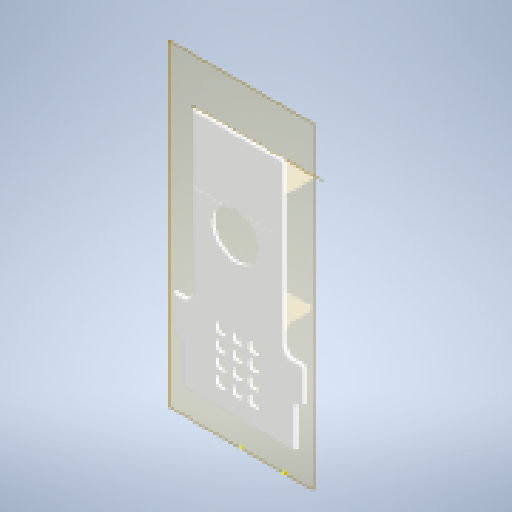
# Autodesk Inventor part: низдляакума
Saved by Autodesk Inventor 2024.2 (Build 282272000, 272)
## iProperties
Created: 2026-09-03
Part Number: низдляакума
Material: PLA
Document SubType Name: Modeling
Designer: katya_notebook
Density: 1.24 g/cm^3
Appearance: Типовые
Author: katya_notebook
Autodesk Inventor part; units mm, degrees
ref_plane "YZ Plane" through (0, 0, 0) normal (1, 0, 0) x (0, 1, 0)
ref_plane "XZ Plane" through (0, 0, 0) normal (0, 1, 0) x (-1, 0, 0)
ref_plane "XY Plane" through (0, 0, 0) normal (0, 0, 1) x (1, 0, 0)
ref_plane "РабПлоскость1" through (0, 0, 0) normal (0, 0, 1) x (1, 0, 0)
sketch "Эскиз1" plane through (0, 0, 0) normal (0, 0, 1) x (1, 0, 0)
  line L0 (-33.5, 89.193196) -> (-33.5, 206.15018)
  line L1 (-33.5, 206.15018) -> (33.5, 206.15018)
  line L2 (33.5, 206.15018) -> (33.5, 89.193196)
  line L3 (33.5, 89.193196) -> (-33.5, 89.193196)
  arc A0 (-15.5, 209.5) -> (-15.5, 222.5) centre (-15.5, 216) ccw
  line L4 (-30.5, 209.5) -> (-15.5, 209.5)
  arc A1 (-30.5, 222.5) -> (-30.5, 209.5) centre (-30.5, 216) ccw
  line L5 (-15.5, 222.5) -> (-30.5, 222.5)
  arc A2 (21.25, 83.001313) -> (23.75, 80.501313) centre (23.75, 83.001313) ccw
  line L6 (21.25, 83.001313) -> (21.25, 85.501313)
  arc A3 (23.75, 88.001313) -> (21.25, 85.501313) centre (23.75, 85.501313) ccw
  line L7 (23.75, 88.001313) -> (26.25, 88.001313)
  arc A4 (28.75, 85.501313) -> (26.25, 88.001313) centre (26.25, 85.501313) ccw
  line L8 (28.75, 85.501313) -> (28.75, 83.001313)
  arc A5 (26.25, 80.501313) -> (28.75, 83.001313) centre (26.25, 83.001313) ccw
  line L9 (26.25, 80.501313) -> (23.75, 80.501313)
  arc A6 (8.75, 83.001313) -> (11.25, 80.501313) centre (11.25, 83.001313) ccw
  line L10 (8.75, 83.001313) -> (8.75, 85.501313)
  arc A7 (11.25, 88.001313) -> (8.75, 85.501313) centre (11.25, 85.501313) ccw
  line L11 (11.25, 88.001313) -> (13.75, 88.001313)
  arc A8 (16.25, 85.501313) -> (13.75, 88.001313) centre (13.75, 85.501313) ccw
  line L12 (16.25, 85.501313) -> (16.25, 83.001313)
  arc A9 (13.75, 80.501313) -> (16.25, 83.001313) centre (13.75, 83.001313) ccw
  line L13 (13.75, 80.501313) -> (11.25, 80.501313)
  arc A10 (-3.75, 83.001313) -> (-1.25, 80.501313) centre (-1.25, 83.001313) ccw
  line L14 (-3.75, 83.001313) -> (-3.75, 85.501313)
  arc A11 (-1.25, 88.001313) -> (-3.75, 85.501313) centre (-1.25, 85.501313) ccw
  line L15 (-1.25, 88.001313) -> (1.25, 88.001313)
  arc A12 (3.75, 85.501313) -> (1.25, 88.001313) centre (1.25, 85.501313) ccw
  line L16 (3.75, 85.501313) -> (3.75, 83.001313)
  arc A13 (1.25, 80.501313) -> (3.75, 83.001313) centre (1.25, 83.001313) ccw
  line L17 (1.25, 80.501313) -> (-1.25, 80.501313)
  arc A14 (-16.25, 83.001313) -> (-13.75, 80.501313) centre (-13.75, 83.001313) ccw
  line L18 (-16.25, 83.001313) -> (-16.25, 85.501313)
  arc A15 (-13.75, 88.001313) -> (-16.25, 85.501313) centre (-13.75, 85.501313) ccw
  line L19 (-13.75, 88.001313) -> (-11.25, 88.001313)
  arc A16 (-8.75, 85.501313) -> (-11.25, 88.001313) centre (-11.25, 85.501313) ccw
  line L20 (-8.75, 85.501313) -> (-8.75, 83.001313)
  arc A17 (-11.25, 80.501313) -> (-8.75, 83.001313) centre (-11.25, 83.001313) ccw
  line L21 (-11.25, 80.501313) -> (-13.75, 80.501313)
  arc A18 (-28.75, 83.001313) -> (-26.25, 80.501313) centre (-26.25, 83.001313) ccw
  line L22 (-28.75, 83.001313) -> (-28.75, 85.501313)
  arc A19 (-26.25, 88.001313) -> (-28.75, 85.501313) centre (-26.25, 85.501313) ccw
  line L23 (-26.25, 88.001313) -> (-23.75, 88.001313)
  arc A20 (-21.25, 85.501313) -> (-23.75, 88.001313) centre (-23.75, 85.501313) ccw
  line L24 (-21.25, 85.501313) -> (-21.25, 83.001313)
  arc A21 (-23.75, 80.501313) -> (-21.25, 83.001313) centre (-23.75, 83.001313) ccw
  line L25 (-23.75, 80.501313) -> (-26.25, 80.501313)
  arc A22 (21.25, 71.334646) -> (23.75, 68.834646) centre (23.75, 71.334646) ccw
  line L26 (21.25, 71.334646) -> (21.25, 73.834646)
  arc A23 (23.75, 76.334646) -> (21.25, 73.834646) centre (23.75, 73.834646) ccw
  line L27 (23.75, 76.334646) -> (26.25, 76.334646)
  arc A24 (28.75, 73.834646) -> (26.25, 76.334646) centre (26.25, 73.834646) ccw
  line L28 (28.75, 73.834646) -> (28.75, 71.334646)
  arc A25 (26.25, 68.834646) -> (28.75, 71.334646) centre (26.25, 71.334646) ccw
  line L29 (26.25, 68.834646) -> (23.75, 68.834646)
  arc A26 (8.75, 71.334646) -> (11.25, 68.834646) centre (11.25, 71.334646) ccw
  line L30 (8.75, 71.334646) -> (8.75, 73.834646)
  arc A27 (11.25, 76.334646) -> (8.75, 73.834646) centre (11.25, 73.834646) ccw
  line L31 (11.25, 76.334646) -> (13.75, 76.334646)
  arc A28 (16.25, 73.834646) -> (13.75, 76.334646) centre (13.75, 73.834646) ccw
  line L32 (16.25, 73.834646) -> (16.25, 71.334646)
  arc A29 (13.75, 68.834646) -> (16.25, 71.334646) centre (13.75, 71.334646) ccw
  line L33 (13.75, 68.834646) -> (11.25, 68.834646)
  arc A30 (-3.75, 71.334646) -> (-1.25, 68.834646) centre (-1.25, 71.334646) ccw
  line L34 (-3.75, 71.334646) -> (-3.75, 73.834646)
  arc A31 (-1.25, 76.334646) -> (-3.75, 73.834646) centre (-1.25, 73.834646) ccw
  line L35 (-1.25, 76.334646) -> (1.25, 76.334646)
  arc A32 (3.75, 73.834646) -> (1.25, 76.334646) centre (1.25, 73.834646) ccw
  line L36 (3.75, 73.834646) -> (3.75, 71.334646)
  arc A33 (1.25, 68.834646) -> (3.75, 71.334646) centre (1.25, 71.334646) ccw
  line L37 (1.25, 68.834646) -> (-1.25, 68.834646)
  arc A34 (-16.25, 71.334646) -> (-13.75, 68.834646) centre (-13.75, 71.334646) ccw
  line L38 (-16.25, 71.334646) -> (-16.25, 73.834646)
  arc A35 (-13.75, 76.334646) -> (-16.25, 73.834646) centre (-13.75, 73.834646) ccw
  line L39 (-13.75, 76.334646) -> (-11.25, 76.334646)
  arc A36 (-8.75, 73.834646) -> (-11.25, 76.334646) centre (-11.25, 73.834646) ccw
  line L40 (-8.75, 73.834646) -> (-8.75, 71.334646)
  arc A37 (-11.25, 68.834646) -> (-8.75, 71.334646) centre (-11.25, 71.334646) ccw
  line L41 (-11.25, 68.834646) -> (-13.75, 68.834646)
  arc A38 (-28.75, 71.334646) -> (-26.25, 68.834646) centre (-26.25, 71.334646) ccw
  line L42 (-28.75, 71.334646) -> (-28.75, 73.834646)
  arc A39 (-26.25, 76.334646) -> (-28.75, 73.834646) centre (-26.25, 73.834646) ccw
  line L43 (-26.25, 76.334646) -> (-23.75, 76.334646)
  arc A40 (-21.25, 73.834646) -> (-23.75, 76.334646) centre (-23.75, 73.834646) ccw
  line L44 (-21.25, 73.834646) -> (-21.25, 71.334646)
  arc A41 (-23.75, 68.834646) -> (-21.25, 71.334646) centre (-23.75, 71.334646) ccw
  line L45 (-23.75, 68.834646) -> (-26.25, 68.834646)
  arc A42 (21.25, 59.66798) -> (23.75, 57.16798) centre (23.75, 59.66798) ccw
  line L46 (21.25, 59.66798) -> (21.25, 62.16798)
  arc A43 (23.75, 64.66798) -> (21.25, 62.16798) centre (23.75, 62.16798) ccw
  line L47 (23.75, 64.66798) -> (26.25, 64.66798)
  arc A44 (28.75, 62.16798) -> (26.25, 64.66798) centre (26.25, 62.16798) ccw
  line L48 (28.75, 62.16798) -> (28.75, 59.66798)
  arc A45 (26.25, 57.16798) -> (28.75, 59.66798) centre (26.25, 59.66798) ccw
  line L49 (26.25, 57.16798) -> (23.75, 57.16798)
  arc A46 (8.75, 59.66798) -> (11.25, 57.16798) centre (11.25, 59.66798) ccw
  line L50 (8.75, 59.66798) -> (8.75, 62.16798)
  arc A47 (11.25, 64.66798) -> (8.75, 62.16798) centre (11.25, 62.16798) ccw
  line L51 (11.25, 64.66798) -> (13.75, 64.66798)
  arc A48 (16.25, 62.16798) -> (13.75, 64.66798) centre (13.75, 62.16798) ccw
  line L52 (16.25, 62.16798) -> (16.25, 59.66798)
  arc A49 (13.75, 57.16798) -> (16.25, 59.66798) centre (13.75, 59.66798) ccw
  line L53 (13.75, 57.16798) -> (11.25, 57.16798)
  arc A50 (-3.75, 59.66798) -> (-1.25, 57.16798) centre (-1.25, 59.66798) ccw
  line L54 (-3.75, 59.66798) -> (-3.75, 62.16798)
  arc A51 (-1.25, 64.66798) -> (-3.75, 62.16798) centre (-1.25, 62.16798) ccw
  line L55 (-1.25, 64.66798) -> (1.25, 64.66798)
  arc A52 (3.75, 62.16798) -> (1.25, 64.66798) centre (1.25, 62.16798) ccw
  line L56 (3.75, 62.16798) -> (3.75, 59.66798)
  arc A53 (1.25, 57.16798) -> (3.75, 59.66798) centre (1.25, 59.66798) ccw
  line L57 (1.25, 57.16798) -> (-1.25, 57.16798)
  arc A54 (-16.25, 59.66798) -> (-13.75, 57.16798) centre (-13.75, 59.66798) ccw
  line L58 (-16.25, 59.66798) -> (-16.25, 62.16798)
  arc A55 (-13.75, 64.66798) -> (-16.25, 62.16798) centre (-13.75, 62.16798) ccw
  line L59 (-13.75, 64.66798) -> (-11.25, 64.66798)
  arc A56 (-8.75, 62.16798) -> (-11.25, 64.66798) centre (-11.25, 62.16798) ccw
  line L60 (-8.75, 62.16798) -> (-8.75, 59.66798)
  arc A57 (-11.25, 57.16798) -> (-8.75, 59.66798) centre (-11.25, 59.66798) ccw
  line L61 (-11.25, 57.16798) -> (-13.75, 57.16798)
  arc A58 (-28.75, 59.66798) -> (-26.25, 57.16798) centre (-26.25, 59.66798) ccw
  line L62 (-28.75, 59.66798) -> (-28.75, 62.16798)
  arc A59 (-26.25, 64.66798) -> (-28.75, 62.16798) centre (-26.25, 62.16798) ccw
  line L63 (-26.25, 64.66798) -> (-23.75, 64.66798)
  arc A60 (-21.25, 62.16798) -> (-23.75, 64.66798) centre (-23.75, 62.16798) ccw
  line L64 (-21.25, 62.16798) -> (-21.25, 59.66798)
  arc A61 (-23.75, 57.16798) -> (-21.25, 59.66798) centre (-23.75, 59.66798) ccw
  line L65 (-23.75, 57.16798) -> (-26.25, 57.16798)
  arc A62 (21.25, 48.001313) -> (23.75, 45.501313) centre (23.75, 48.001313) ccw
  line L66 (21.25, 48.001313) -> (21.25, 50.501313)
  arc A63 (23.75, 53.001313) -> (21.25, 50.501313) centre (23.75, 50.501313) ccw
  line L67 (23.75, 53.001313) -> (26.25, 53.001313)
  arc A64 (28.75, 50.501313) -> (26.25, 53.001313) centre (26.25, 50.501313) ccw
  line L68 (28.75, 50.501313) -> (28.75, 48.001313)
  arc A65 (26.25, 45.501313) -> (28.75, 48.001313) centre (26.25, 48.001313) ccw
  line L69 (26.25, 45.501313) -> (23.75, 45.501313)
  arc A66 (8.75, 48.001313) -> (11.25, 45.501313) centre (11.25, 48.001313) ccw
  line L70 (8.75, 48.001313) -> (8.75, 50.501313)
  arc A67 (11.25, 53.001313) -> (8.75, 50.501313) centre (11.25, 50.501313) ccw
  line L71 (11.25, 53.001313) -> (13.75, 53.001313)
  arc A68 (16.25, 50.501313) -> (13.75, 53.001313) centre (13.75, 50.501313) ccw
  line L72 (16.25, 50.501313) -> (16.25, 48.001313)
  arc A69 (13.75, 45.501313) -> (16.25, 48.001313) centre (13.75, 48.001313) ccw
  line L73 (13.75, 45.501313) -> (11.25, 45.501313)
  arc A70 (-3.75, 48.001313) -> (-1.25, 45.501313) centre (-1.25, 48.001313) ccw
  line L74 (-3.75, 48.001313) -> (-3.75, 50.501313)
  arc A71 (-1.25, 53.001313) -> (-3.75, 50.501313) centre (-1.25, 50.501313) ccw
  line L75 (-1.25, 53.001313) -> (1.25, 53.001313)
  arc A72 (3.75, 50.501313) -> (1.25, 53.001313) centre (1.25, 50.501313) ccw
  line L76 (3.75, 50.501313) -> (3.75, 48.001313)
  arc A73 (1.25, 45.501313) -> (3.75, 48.001313) centre (1.25, 48.001313) ccw
  line L77 (1.25, 45.501313) -> (-1.25, 45.501313)
  arc A74 (-16.25, 48.001313) -> (-13.75, 45.501313) centre (-13.75, 48.001313) ccw
  line L78 (-16.25, 48.001313) -> (-16.25, 50.501313)
  arc A75 (-13.75, 53.001313) -> (-16.25, 50.501313) centre (-13.75, 50.501313) ccw
  line L79 (-13.75, 53.001313) -> (-11.25, 53.001313)
  arc A76 (-8.75, 50.501313) -> (-11.25, 53.001313) centre (-11.25, 50.501313) ccw
  line L80 (-8.75, 50.501313) -> (-8.75, 48.001313)
  arc A77 (-11.25, 45.501313) -> (-8.75, 48.001313) centre (-11.25, 48.001313) ccw
  line L81 (-11.25, 45.501313) -> (-13.75, 45.501313)
  arc A78 (-28.75, 48.001313) -> (-26.25, 45.501313) centre (-26.25, 48.001313) ccw
  line L82 (-28.75, 48.001313) -> (-28.75, 50.501313)
  arc A79 (-26.25, 53.001313) -> (-28.75, 50.501313) centre (-26.25, 50.501313) ccw
  line L83 (-26.25, 53.001313) -> (-23.75, 53.001313)
  arc A80 (-21.25, 50.501313) -> (-23.75, 53.001313) centre (-23.75, 50.501313) ccw
  line L84 (-21.25, 50.501313) -> (-21.25, 48.001313)
  arc A81 (-23.75, 45.501313) -> (-21.25, 48.001313) centre (-23.75, 48.001313) ccw
  line L85 (-23.75, 45.501313) -> (-26.25, 45.501313)
  arc A82 (21.25, 36.334646) -> (23.75, 33.834646) centre (23.75, 36.334646) ccw
  line L86 (21.25, 36.334646) -> (21.25, 38.834646)
  arc A83 (23.75, 41.334646) -> (21.25, 38.834646) centre (23.75, 38.834646) ccw
  line L87 (23.75, 41.334646) -> (26.25, 41.334646)
  arc A84 (28.75, 38.834646) -> (26.25, 41.334646) centre (26.25, 38.834646) ccw
  line L88 (28.75, 38.834646) -> (28.75, 36.334646)
  arc A85 (26.25, 33.834646) -> (28.75, 36.334646) centre (26.25, 36.334646) ccw
  line L89 (26.25, 33.834646) -> (23.75, 33.834646)
  arc A86 (8.75, 36.334646) -> (11.25, 33.834646) centre (11.25, 36.334646) ccw
  line L90 (8.75, 36.334646) -> (8.75, 38.834646)
  arc A87 (11.25, 41.334646) -> (8.75, 38.834646) centre (11.25, 38.834646) ccw
  line L91 (11.25, 41.334646) -> (13.75, 41.334646)
  arc A88 (16.25, 38.834646) -> (13.75, 41.334646) centre (13.75, 38.834646) ccw
  line L92 (16.25, 38.834646) -> (16.25, 36.334646)
  arc A89 (13.75, 33.834646) -> (16.25, 36.334646) centre (13.75, 36.334646) ccw
  line L93 (13.75, 33.834646) -> (11.25, 33.834646)
  arc A90 (-3.75, 36.334646) -> (-1.25, 33.834646) centre (-1.25, 36.334646) ccw
  line L94 (-3.75, 36.334646) -> (-3.75, 38.834646)
  arc A91 (-1.25, 41.334646) -> (-3.75, 38.834646) centre (-1.25, 38.834646) ccw
  line L95 (-1.25, 41.334646) -> (1.25, 41.334646)
  arc A92 (3.75, 38.834646) -> (1.25, 41.334646) centre (1.25, 38.834646) ccw
  line L96 (3.75, 38.834646) -> (3.75, 36.334646)
  arc A93 (1.25, 33.834646) -> (3.75, 36.334646) centre (1.25, 36.334646) ccw
  line L97 (1.25, 33.834646) -> (-1.25, 33.834646)
  arc A94 (-16.25, 36.334646) -> (-13.75, 33.834646) centre (-13.75, 36.334646) ccw
  line L98 (-16.25, 36.334646) -> (-16.25, 38.834646)
  arc A95 (-13.75, 41.334646) -> (-16.25, 38.834646) centre (-13.75, 38.834646) ccw
  line L99 (-13.75, 41.334646) -> (-11.25, 41.334646)
  arc A96 (-8.75, 38.834646) -> (-11.25, 41.334646) centre (-11.25, 38.834646) ccw
  line L100 (-8.75, 38.834646) -> (-8.75, 36.334646)
  arc A97 (-11.25, 33.834646) -> (-8.75, 36.334646) centre (-11.25, 36.334646) ccw
  line L101 (-11.25, 33.834646) -> (-13.75, 33.834646)
  arc A98 (21.25, 24.66798) -> (23.75, 22.16798) centre (23.75, 24.66798) ccw
  line L102 (21.25, 24.66798) -> (21.25, 27.16798)
  arc A99 (23.75, 29.66798) -> (21.25, 27.16798) centre (23.75, 27.16798) ccw
  line L103 (23.75, 29.66798) -> (26.25, 29.66798)
  arc A100 (28.75, 27.16798) -> (26.25, 29.66798) centre (26.25, 27.16798) ccw
  line L104 (28.75, 27.16798) -> (28.75, 24.66798)
  arc A101 (26.25, 22.16798) -> (28.75, 24.66798) centre (26.25, 24.66798) ccw
  line L105 (26.25, 22.16798) -> (23.75, 22.16798)
  arc A102 (8.75, 24.66798) -> (11.25, 22.16798) centre (11.25, 24.66798) ccw
  line L106 (8.75, 24.66798) -> (8.75, 27.16798)
  arc A103 (11.25, 29.66798) -> (8.75, 27.16798) centre (11.25, 27.16798) ccw
  line L107 (11.25, 29.66798) -> (13.75, 29.66798)
  arc A104 (16.25, 27.16798) -> (13.75, 29.66798) centre (13.75, 27.16798) ccw
  line L108 (16.25, 27.16798) -> (16.25, 24.66798)
  arc A105 (13.75, 22.16798) -> (16.25, 24.66798) centre (13.75, 24.66798) ccw
  line L109 (13.75, 22.16798) -> (11.25, 22.16798)
  arc A106 (-3.75, 24.66798) -> (-1.25, 22.16798) centre (-1.25, 24.66798) ccw
  line L110 (-3.75, 24.66798) -> (-3.75, 27.16798)
  arc A107 (-1.25, 29.66798) -> (-3.75, 27.16798) centre (-1.25, 27.16798) ccw
  line L111 (-1.25, 29.66798) -> (1.25, 29.66798)
  arc A108 (3.75, 27.16798) -> (1.25, 29.66798) centre (1.25, 27.16798) ccw
  line L112 (3.75, 27.16798) -> (3.75, 24.66798)
  arc A109 (1.25, 22.16798) -> (3.75, 24.66798) centre (1.25, 24.66798) ccw
  line L113 (1.25, 22.16798) -> (-1.25, 22.16798)
  arc A110 (-16.25, 24.66798) -> (-13.75, 22.16798) centre (-13.75, 24.66798) ccw
  line L114 (-16.25, 24.66798) -> (-16.25, 27.16798)
  arc A111 (-13.75, 29.66798) -> (-16.25, 27.16798) centre (-13.75, 27.16798) ccw
  line L115 (-13.75, 29.66798) -> (-11.25, 29.66798)
  arc A112 (-8.75, 27.16798) -> (-11.25, 29.66798) centre (-11.25, 27.16798) ccw
  line L116 (-8.75, 27.16798) -> (-8.75, 24.66798)
  arc A113 (-11.25, 22.16798) -> (-8.75, 24.66798) centre (-11.25, 24.66798) ccw
  line L117 (-11.25, 22.16798) -> (-13.75, 22.16798)
  line L118 (-23.75, 33.834646) -> (-26.25, 33.834646)
  arc A114 (-28.75, 36.334646) -> (-26.25, 33.834646) centre (-26.25, 36.334646) ccw
  line L119 (-28.75, 36.334646) -> (-28.75, 38.834646)
  arc A115 (-26.25, 41.334646) -> (-28.75, 38.834646) centre (-26.25, 38.834646) ccw
  line L120 (-26.25, 41.334646) -> (-23.75, 41.334646)
  arc A116 (-21.25, 38.834646) -> (-23.75, 41.334646) centre (-23.75, 38.834646) ccw
  line L121 (-21.25, 38.834646) -> (-21.25, 36.334646)
  arc A117 (-23.75, 33.834646) -> (-21.25, 36.334646) centre (-23.75, 36.334646) ccw
  arc A118 (15.5, 222.5) -> (15.5, 209.5) centre (15.5, 216) ccw
  line L122 (30.5, 222.5) -> (15.5, 222.5)
  arc A119 (30.5, 209.5) -> (30.5, 222.5) centre (30.5, 216) ccw
  line L123 (15.5, 209.5) -> (30.5, 209.5)
  arc A120 (-28.75, 24.66798) -> (-26.25, 22.16798) centre (-26.25, 24.66798) ccw
  line L124 (-28.75, 24.66798) -> (-28.75, 27.16798)
  arc A121 (-26.25, 29.66798) -> (-28.75, 27.16798) centre (-26.25, 27.16798) ccw
  line L125 (-26.25, 29.66798) -> (-23.75, 29.66798)
  arc A122 (-21.25, 27.16798) -> (-23.75, 29.66798) centre (-23.75, 27.16798) ccw
  line L126 (-21.25, 27.16798) -> (-21.25, 24.66798)
  arc A123 (-23.75, 22.16798) -> (-21.25, 24.66798) centre (-23.75, 24.66798) ccw
  line L127 (-23.75, 22.16798) -> (-26.25, 22.16798)
  line L128 (40.32, 10.796198) -> (40.32, 19.614214)
  line L129 (43.52, 19.614214) -> (40.32, 19.614214)
  line L130 (43.52, 47.889632) -> (43.52, 19.614214)
  line L131 (43.52, 48.889632) -> (43.52, 47.889632)
  spline S0 degree 3 poles (46.52, 52.718059) (45.988293, 52.718059) (45.465608, 52.533743) (44.747547, 52.02148) (44.497025, 51.760764) (44.28929, 51.466982) (44.081555, 51.173201) (43.916043, 50.845952) (43.611007, 49.990786) (43.52, 49.440225) (43.52, 48.889632) knots 0 0 0 0 0.46720011 0.46720011 0.78539816 0.78539816 0.78539816 1.10359621 1.10359621 1.57079633 1.57079633 1.57079633 1.57079633 weights 1 1 1 1 1 1 1 1 1 1 1
  line L132 (50, 52.718059) -> (46.52, 52.718059)
  line L133 (50, 79.281941) -> (50, 52.718059)
  line L134 (40.223427, 79.281941) -> (50, 79.281941)
  spline S1 degree 3 poles (37.992717, 80.533018) (38.090301, 80.395012) (38.197257, 80.26438) (38.50255, 79.945668) (38.716535, 79.772676) (38.952611, 79.634386) (39.14321, 79.522735) (39.348233, 79.433912) (39.776672, 79.31339) (39.999967, 79.281941) (40.223427, 79.281941) knots -0.78539816 -0.78539816 -0.78539816 -0.78539816 -0.63589713 -0.63589713 -0.39269908 -0.39269908 -0.39269908 -0.19634954 -0.19634954 0 0 0 0 weights 1 1 1 1 1 1 1 1 1 1 1
  line L135 (37.584469, 81.110368) -> (37.992717, 80.533018)
  line L136 (35.58929, 83.931977) -> (37.584469, 81.110368)
  spline S2 degree 3 poles (35.068542, 84.968313) (35.131458, 84.782315) (35.206295, 84.601573) (35.379847, 84.254704) (35.478568, 84.088561) (35.58929, 83.931977) knots 0 0 0 0 0.5 0.5 1 1 1 1 weights 1 1 1 1 1 1
  spline S3 degree 3 poles (34.82, 86.509327) (34.82, 86.482405) (34.820217, 86.455483) (34.827693, 85.992767) (34.89176, 85.55828) (35.012558, 85.14585) (35.030032, 85.086189) (35.048694, 85.02699) (35.068542, 84.968313) knots 0 0 0 0 0.05119683 0.05119683 0.88009386 0.88009386 0.88009386 1 1 1 1 weights 1 1 1 1 1 1 1 1 1
  line L137 (34.82, 87.509327) -> (34.82, 86.509327)
  line L138 (34.82, 197.889632) -> (34.82, 87.509327)
  line L139 (34.82, 198.889632) -> (34.82, 197.889632)
  spline S4 degree 3 poles (37.82, 202.718059) (37.288293, 202.718059) (36.765608, 202.533743) (36.047547, 202.02148) (35.797025, 201.760764) (35.58929, 201.466982) (35.381555, 201.173201) (35.216043, 200.845952) (34.911007, 199.990786) (34.82, 199.440225) (34.82, 198.889632) knots 0 0 0 0 0.46720011 0.46720011 0.78539816 0.78539816 0.78539816 1.10359621 1.10359621 1.57079633 1.57079633 1.57079633 1.57079633 weights 1 1 1 1 1 1 1 1 1 1 1
  line L140 (39, 202.718059) -> (37.82, 202.718059)
  line L141 (39, 229.281941) -> (39, 202.718059)
  line L142 (-39, 229.281941) -> (39, 229.281941)
  line L143 (-39, 202.718059) -> (-39, 229.281941)
  line L144 (-37.82, 202.718059) -> (-39, 202.718059)
  spline S5 degree 3 poles (-34.82, 198.889632) (-34.82, 199.440225) (-34.911007, 199.990786) (-35.216043, 200.845952) (-35.381555, 201.173201) (-35.58929, 201.466982) (-35.797025, 201.760764) (-36.047547, 202.02148) (-36.765608, 202.533743) (-37.288293, 202.718059) (-37.82, 202.718059) knots -1.57079633 -1.57079633 -1.57079633 -1.57079633 -1.10359621 -1.10359621 -0.78539816 -0.78539816 -0.78539816 -0.46720011 -0.46720011 0 0 0 0 weights 1 1 1 1 1 1 1 1 1 1 1
  line L145 (-34.82, 197.889632) -> (-34.82, 198.889632)
  line L146 (-34.82, 87.509327) -> (-34.82, 197.889632)
  line L147 (-34.82, 86.509327) -> (-34.82, 87.509327)
  spline S6 degree 3 poles (-35.068542, 84.968313) (-35.048694, 85.02699) (-35.030032, 85.086189) (-35.012558, 85.14585) (-34.89176, 85.55828) (-34.827693, 85.992767) (-34.820217, 86.455483) (-34.82, 86.482405) (-34.82, 86.509327) knots 0 0 0 0 0.11990614 0.11990614 0.11990614 0.94880317 0.94880317 1 1 1 1 weights 1 1 1 1 1 1 1 1 1
  spline S7 degree 3 poles (-35.58929, 83.931977) (-35.478568, 84.088561) (-35.379847, 84.254704) (-35.206295, 84.601573) (-35.131458, 84.782315) (-35.068542, 84.968313) knots 0 0 0 0 0.5 0.5 1 1 1 1 weights 1 1 1 1 1 1
  line L148 (-37.584469, 81.110368) -> (-35.58929, 83.931977)
  line L149 (-37.992717, 80.533018) -> (-37.584469, 81.110368)
  spline S8 degree 3 poles (-40.223427, 79.281941) (-39.999967, 79.281941) (-39.776672, 79.31339) (-39.348233, 79.433912) (-39.14321, 79.522735) (-38.952611, 79.634386) (-38.716535, 79.772676) (-38.50255, 79.945668) (-38.197257, 80.26438) (-38.090301, 80.395012) (-37.992717, 80.533018) knots 0 0 0 0 0.19634954 0.19634954 0.39269908 0.39269908 0.39269908 0.63589713 0.63589713 0.78539816 0.78539816 0.78539816 0.78539816 weights 1 1 1 1 1 1 1 1 1 1 1
  line L150 (-50, 79.281941) -> (-40.223427, 79.281941)
  line L151 (-50, 52.718059) -> (-50, 79.281941)
  line L152 (-46.52, 52.718059) -> (-50, 52.718059)
  spline S9 degree 3 poles (-43.52, 48.889632) (-43.52, 49.440225) (-43.611007, 49.990786) (-43.916043, 50.845952) (-44.081555, 51.173201) (-44.28929, 51.466982) (-44.497025, 51.760764) (-44.747547, 52.02148) (-45.465608, 52.533743) (-45.988293, 52.718059) (-46.52, 52.718059) knots -1.57079633 -1.57079633 -1.57079633 -1.57079633 -1.10359621 -1.10359621 -0.78539816 -0.78539816 -0.78539816 -0.46720011 -0.46720011 0 0 0 0 weights 1 1 1 1 1 1 1 1 1 1 1
  line L153 (-43.52, 47.889632) -> (-43.52, 48.889632)
  line L154 (-43.52, 19.614214) -> (-43.52, 47.889632)
  line L155 (-40.32, 19.614214) -> (-43.52, 19.614214)
  line L156 (-40.32, 19.614214) -> (-40.32, 10.796198)
  line L157 (-36.996804, 10.796198) -> (-40.32, 10.796198)
  arc A124 (-30.5, 17.5) -> (-36.996804, 10.796198) centre (-30.5, 11) ccw
  line L158 (-15.5, 17.5) -> (-30.5, 17.5)
  arc A125 (-9.003196, 10.796198) -> (-15.5, 17.5) centre (-15.5, 11) ccw
  line L159 (9.003196, 10.796198) -> (-9.003196, 10.796198)
  arc A126 (15.5, 17.5) -> (9.003196, 10.796198) centre (15.5, 11) ccw
  line L160 (30.5, 17.5) -> (15.5, 17.5)
  arc A127 (36.996804, 10.796198) -> (30.5, 17.5) centre (30.5, 11) ccw
  line L161 (40.32, 10.796198) -> (36.996804, 10.796198)
  line L162 (35.82, 87.509327) -> (35.82, 197.889632)
  line L163 (-35.82, 197.889632) -> (-35.82, 87.509327)
  line L164 (-35.82, 197.889632) -> (-35.82, 87.509327)
  line L165 (33.5, 206.15018) -> (39, 206.15018)
  line L166 (-33.5, 206.15018) -> (-39, 206.15018)
  point P0 (0, 0)
  constraints: 4 end point, 3 point on line, 1 perpendicular
extrude "Выдавливание1" add sketch "Эскиз1" along normal blind 2 contours L3 L2 L165 L141 L140 S4 L139 L138 L137 S3 S2 L136 L135 S1 L134 L133 L132 S0 L131 L130 L129 L128 L161 A127 L160 A126 L159 A125 L158 A124 L157 L156 L155 L154 L153 S9 L152 L151 L150 S8 L149 L148 S7 S6 L147 L146 L145 S5 L144 L143 L166 L0 | L0 L1 L2 L3 | L6 A3 L7 A4 L8 A5 L9 A2 | L10 A7 L11 A8 L12 A9 L13 A6 | L14 A11 L15 A12 L16 A13 L17 A10 | L18 A15 L19 A16 L20 A17 L21 A14 | L22 A19 L23 A20 L24 A21 L25 A18 | L26 A23 L27 A24 L28 A25 L29 A22 | L42 A39 L43 A40 L44 A41 L45 A38 | L46 A43 L47 A44 L48 A45 L49 A42 | L62 A59 L63 A60 L64 A61 L65 A58 | L66 A63 L67 A64 L68 A65 L69 A62 | L82 A79 L83 A80 L84 A81 L85 A78 | L86 A83 L87 A84 L88 A85 L89 A82 | L102 A99 L103 A100 L104 A101 L105 A98 | L106 A103 L107 A104 L108 A105 L109 A102 | L110 A107 L111 A108 L112 A109 L113 A106 | L114 A111 L115 A112 L116 A113 L117 A110 | L118 A114 L119 A115 L120 A116 L121 A117 | L124 A121 L125 A122 L126 A123 L127 A120
ref_plane "РабПлоскость2" through (0, 206.97018, 0.82) normal (0, -0.7071068, 0.7071068) x (1, 0, 0)
sketch "Эскиз2" plane through (0, 206.97018, 0.82) normal (0, -0.7071068, 0.7071068) x (1, 0, 0)
  line L0 (-34.376709, -3.481439) -> (-34.278434, -35.966031)
  line L1 (-34.278434, -35.966031) -> (32.720953, -35.763338)
  line L2 (32.622678, -3.278746) -> (32.720953, -35.763338)
  line L3 (32.622678, -3.278746) -> (-34.376709, -3.481439)
  point P0 (0, -146.929846)
extrude "Выдавливание2" add sketch "Эскиз2" along normal blind 64.5
sketch "Эскиз3" plane through (34.82, 86.509327, 0) normal (1, 0, 0) x (0, 0, -1)
  line L0 (-2, 114.644006) -> (-2, 68.703856)
  line L1 (-2, 114.644006) -> (-44.109964, 72.534042)
  line L2 (-21.139889, 49.563967) -> (-44.109964, 72.534042)
  line L3 (-2, 68.703856) -> (-21.139889, 49.563967)
  point P0 (0, -86.509327)
extrude "Выдавливание3" cut sketch "Эскиз3" against normal blind 90.75
sketch "Эскиз4" plane through (0, 0, 2) normal (0, 0, 1) x (1, 0, 0)
  line L0 (40.32, 10.796198) -> (40.32, 19.614214)
  line L1 (-40.32, 10.796198) -> (-36.996804, 10.796198)
  line L2 (40.32, 19.614214) -> (-40.32, 19.614214)
  line L3 (-40.32, 19.614214) -> (-40.32, 10.796198)
  line L4 (-40.32, 10.796198) -> (40.32, 10.796198)
  line L5 (40.32, 10.796198) -> (40.32, 19.614214)
  point P0 (0, 0)
  constraints: 8 end point, 2 parallel, 1 horizontal, 1 perpendicular
extrude "Выдавливание4" cut sketch "Эскиз4" against normal blind 10
sketch "Эскиз5" plane through (0, 0, 2) normal (0, 0, 1) x (1, 0, 0)
  line L0 (-34.82, 198.889632) -> (-34.82, 86.509327)
  line L1 (-39, 206.15018) -> (-39, 202.718059)
  line L2 (-34.82, 198.889632) -> (-39, 198.889632)
  line L3 (-39, 198.889632) -> (-39, 206.15018)
  line L4 (-39, 206.15018) -> (-34.82, 206.15018)
  line L5 (-34.82, 206.15018) -> (-34.82, 198.889632)
  line L6 (39, 202.718059) -> (39, 206.15018)
  line L7 (34.82, 198.889632) -> (39, 198.889632)
  line L8 (39, 198.889632) -> (39, 206.15018)
  line L9 (39, 206.15018) -> (34.82, 206.15018)
  line L10 (34.82, 206.15018) -> (34.82, 198.889632)
  point P0 (0, 0)
  constraints: 16 end point, 4 parallel, 2 horizontal, 2 perpendicular, 1 coincident
extrude "Выдавливание5" cut sketch "Эскиз5" against normal blind 10
fillet "Сопряжение1" radius 1.9 21 edges at (-44.2893, 51.467, 2) (-48.26, 52.7181, 2) (-43.52, 34.2519, 2) (-50, 66, 2) (-45.1117, 79.2819, 2) (-36.791, 82.2325, 2) (-35.2931, 84.4281, 2) (-34.8822, 85.7251, 2) (-34.82, 146.3298, 2) (-38.9526, 79.6344, 2) (44.2893, 51.467, 2) (48.26, 52.7181, 2) (43.52, 34.2519, 2) (50, 66, 2) (38.9526, 79.6344, 2) (36.791, 82.2325, 2) (35.2931, 84.4281, 2) (34.8822, 85.7251, 2) (34.82, 146.3298, 2) (45.1117, 79.2819, 2) (0, 206.1502, 2)
fillet "Сопряжение2" radius 1.9 14 edges at (-43.52, 19.6142, 0.05) (43.52, 19.6142, 0.05) (50, 52.7181, 0.05) (49.4435, 53.2746, 1.4435) (50, 79.2819, 0.05) (49.4435, 78.7254, 1.4435) (34.82, 206.1502, 0.05) (34.2635, 205.5937, 1.4435) (-34.82, 206.1502, 0.05) (-34.2635, 205.5937, 1.4435) (-50, 79.2819, 0.05) (-49.4435, 78.7254, 1.4435) (-50, 52.7181, 0.05) (-49.4435, 53.2746, 1.4435)
sketch "Эскиз6" plane through (0, 0, 2) normal (0, 0, 1) x (1, 0, 0)
  circle A0 centre (-1.714832, 139.377578) radius 11.1
  circle A1 centre (-1.714832, 139.377578) radius 17.5
  point P0 (0, 0)
  dimension "d12" = 35
  constraints: 1 centre point, 1 coincident
  measures "d12" diameter of A1
sketch "Эскиз7" plane through (0, 0, 0) normal (0, 0, -1) x (-1, 0, 0)
  line L0 (-23.596388, 107.159174) -> (24.803612, 107.159174)
  line L1 (-33.086861, 100.159174) -> (33.913752, 100.159174)
  line L2 (33.913752, 100.159174) -> (33.913752, 96.159174)
  line L3 (33.913752, 96.159174) -> (-33.086861, 96.159174)
  line L4 (-33.086861, 96.159174) -> (-33.086861, 100.159174)
  line L5 (-32.61626, 206.153319) -> (-33.116646, 89.197406)
  line L6 (33.88274, 88.910754) -> (34.383127, 205.866668)
  point P0 (0, 0)
  dimension "d13" = 7
  dimension "d14" = 4
  constraints: 8 end point, 2 parallel, 2 point on line, 1 horizontal, 1 perpendicular
  measures "d13" distance between parallel lines of L1 L0
  measures "d14" distance of L3.end L1.start
extrude "Выдавливание6" add sketch "Эскиз7" along normal blind 20
extrude "Выдавливание7" cut sketch "Эскиз6" against normal blind 20 contours A0 | A1
chamfer "Фаска1" distance 5 angle 45 2 edges at (-0.4134, 96.1592, 0) (-0.4134, 100.1592, 0)
sketch "Эскиз8" plane through (0, 0, 0) normal (0, 0, -1) x (-1, 0, 0)
  line L0 (34.278434, 181.538356) -> (-32.720953, 181.681681)
  point P0 (0, 0)
sketch "Эскиз9" plane through (0, 0, 0) normal (0, 0, -1) x (-1, 0, 0)
  line L0 (34.278434, 181.538356) -> (-32.720953, 181.681681)
  line L1 (34.82, 86.509327) -> (34.82, 204.25018)
  line L2 (-34.82, 86.509327) -> (-34.82, 204.25018)
  line L3 (34.82, 181.68) -> (-34.82, 181.68)
  line L4 (-34.82, 181.68) -> (-34.82, 156.798255)
  line L5 (-34.82, 156.798255) -> (34.82, 156.798255)
  line L6 (34.82, 156.798255) -> (34.82, 181.68)
  point P0 (0, 0)
  point P1 (33.5, 181.68)
  point P2 (-31.934919, 181.68)
  constraints: 8 end point, 2 parallel, 2 point on line, 1 horizontal, 1 perpendicular
extrude "Выдавливание8" cut sketch "Эскиз9" along normal blind 39.75
sketch "Эскиз13" plane through (-34.278434, 135.929968, 20.996563) normal (0.0030253, -0.7071035, -0.7071035) x (0.9999954, 0.0021392, 0.0021392)
  line L0 (66.999693, -27.06789) -> (40.251114, -26.986968)
  line L1 (66.999693, -27.06789) -> (66.999693, 0)
  line L2 (0, 0) -> (66.999693, 0)
  line L3 (0, 0) -> (0, -27.673556)
  ellipse E0 centre (1.35844, -29.556312) end of major axis (1.350311, -26.869307) minor radius 1.9 (1.35844, -26.869307) -> (0, -27.673556) ccw
  line L4 (24.742147, -26.940049) -> (1.35844, -26.869307)
  line L5 (40.251114, -26.986968) -> (24.742147, -26.940049)
  point P0 (33.94258, 81.27019)
  constraints: 1 other
extrude "Выдавливание10" cut sketch "Эскиз13" against normal blind 10
sketch "Эскиз14" plane through (32.720953, 181.681681, -24.468499) normal (0.9999954, 0.0021392, 0.0021392) x (0, 0.7071068, -0.7071068)
  point P0 (-145.77019, -111.067009)
